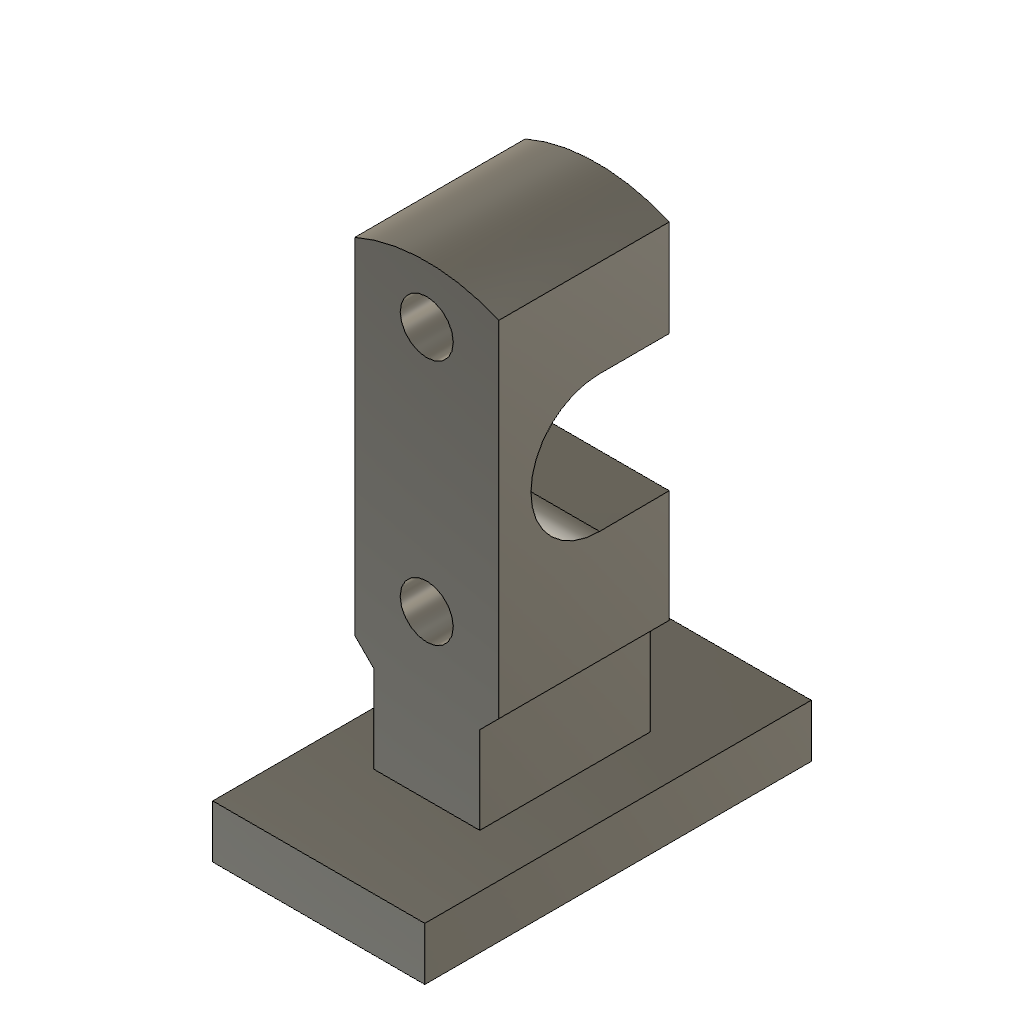
body (Autodesk Fusion 360 design; units mm, degrees)
part number: 2026-10-08-13-23-09-316
Autodesk Fusion 360 part; units mm, degrees
sketch "Sketch1" plane through (0, 0, 0) normal (1, 0, 0) x (0, 1, 0)
  line L0 (0, 0) -> (90, 0)
  line L1 (90, 190) -> (0, 190)
  line L2 (0, 190) -> (0, 0)
  line L3 (90, 0) -> (90, 59.2435)
  line L4 (90, 95) -> (89, 95)
  line L5 (53, 131) -> (90, 131)
  line L6 (53.2376, 59.0008) -> (90, 59.2435)
  arc A0 (53, 131) -> (53.2376, 59.0008) centre (53, 95) ccw
  line L7 (90, 0) -> (90, 59.2435)
  line L8 (90, 131) -> (90, 190)
  line L9 (0, 0) -> (90, 0)
  line L10 (90, 0) -> (90, -56)
  line L11 (90, -56) -> (0, -56)
  line L12 (0, -56) -> (0, 0)
  line L13 (90, -56) -> (147, -56)
  line L14 (147, -56) -> (147, -84)
  line L15 (147, -84) -> (90, -84)
  line L16 (0, -56) -> (-57, -56)
  line L17 (-57, -56) -> (-57, -84)
  line L18 (-57, -84) -> (0, -84)
  line L19 (-57, -56) -> (147, -56)
  line L20 (147, -56) -> (147, -84)
  line L21 (147, -84) -> (-57, -84)
  line L22 (-57, -84) -> (-57, -56)
  dimension "d1" = 90
  dimension "d2" = 190
  dimension "d3" = 95
  dimension "d4" = 37
  dimension "d5" = 72
  dimension "d6" = 90
  dimension "d7" = 56
  dimension "d8" = 57
  dimension "d9" = 28
  dimension "d10" = 57
  dimension "d11" = 28
  constraint horizontal L0
  constraint vertical L7
  constraint horizontal L1
  constraint vertical L2
  constraint coincident L0.start L2.end
  constraint perpendicular L0 L3
  constraint perpendicular L4 L7
  constraint perpendicular L5 L8
  constraint tangent L5 A0
  constraint tangent L6 A0
  constraint collinear L7 L8
  constraint horizontal L9
  constraint vertical L10
  constraint horizontal L11
  constraint vertical L12
  constraint horizontal L13
  constraint vertical L14
  constraint horizontal L15
  constraint horizontal L16
  constraint vertical L17
  constraint horizontal L18
  constraint horizontal L19
  constraint vertical L20
  constraint horizontal L21
  constraint vertical L22
  measures "d1" distance of L0.start L0.end
  measures "d2" distance of L0.start L1.end
  measures "d3" distance of L0.end L4.start
  measures "d4" distance of L4.start A0.centre
  measures "d5" diameter of A0
  measures "d6" distance of L0.start L0.end
  measures "d7" distance of L0.start L11.end
  measures "d8" distance of L10.end L13.end
  measures "d9" distance of L10.end L15.end
  measures "d10" distance of L11.end L16.end
  measures "d11" distance of L11.end L18.end
extrude "Extrude1" add sketch "Sketch1" along normal blind 76 contours L0 L1 L2 L3 L5 L6 A0 L7 L8 L9
sketch "Sketch2" plane through (0, 0, 0) normal (0, -1, 0) x (1, 0, 0)
  line L0 (0, 190) -> (0, 0)
  line L1 (0, 0) -> (76, 0)
  line L2 (76, 0) -> (76, 190)
  line L3 (76, 190) -> (0, 190)
  line L4 (76, 0) -> (66, -10)
  line L5 (76, 0) -> (52.0292, 0) construction
  line L6 (0, 0) -> (10, -10)
  line L7 (0, 0) -> (34.0699, 0) construction
  line L8 (0, 0) -> (10, 0)
  line L9 (10, 0) -> (10, 10)
  line L10 (10, 10) -> (0, 10)
  line L11 (0, 10) -> (0, 0)
  line L12 (10, 0) -> (66, 0)
  line L13 (66, -10) -> (66, -56)
  line L14 (66, -56) -> (10, -56)
  line L15 (10, -56) -> (10, -10)
  dimension "d14" = 45
  dimension "d15" = 45
  dimension "d16" = 10
  dimension "d17" = 10
  dimension "d18" = 56
  dimension "d19" = 56
  constraint horizontal L5
  constraint coincident L1.end L2.start
  constraint horizontal L7
  constraint coincident L0.end L1.start
  constraint horizontal L8
  constraint vertical L9
  constraint horizontal L10
  constraint vertical L11
  constraint horizontal L12
  constraint vertical L13
  constraint horizontal L14
  constraint vertical L15
  measures "d14" angle of L4 L5
  measures "d15" angle of L6 L7
  measures "d16" distance of L0.end L8.end
  measures "d17" distance of L0.end L10.end
  measures "d18" distance of L8.end L12.end
  measures "d19" distance of L8.end L14.end
extrude "Extrude2" add sketch "Sketch2" against normal blind 90 contours L1 L4 L6 L8 L12 L13 L14 L15
sketch "Sketch3" plane through (66, 0, 0) normal (1, 0, 0) x (0, 1, 0)
  line L0 (0, -10) -> (0, -56)
  line L1 (0, -56) -> (90, -56)
  line L2 (90, -56) -> (90, -10)
  line L3 (90, -10) -> (0, -10)
  line L4 (0, -56) -> (-57, -56)
  line L5 (-57, -56) -> (-57, -84)
  line L6 (-57, -84) -> (0, -84)
  line L7 (-57, -56) -> (147, -56)
  line L8 (147, -56) -> (147, -84)
  line L9 (147, -84) -> (-57, -84)
  line L10 (-57, -84) -> (-57, -56)
  dimension "d22" = 57
  dimension "d23" = 28
  dimension "d24" = 204
  dimension "d25" = 28
  constraint horizontal L4
  constraint vertical L5
  constraint horizontal L6
  constraint coincident L0.end L1.start
  constraint horizontal L7
  constraint vertical L8
  constraint horizontal L9
  constraint vertical L10
  measures "d22" distance of L0.end L4.end
  measures "d23" distance of L0.end L6.end
  measures "d24" distance of L4.end L7.end
  measures "d25" distance of L4.end L5.end
extrude "Extrude3" add sketch "Sketch3" along normal blind 28 and the other way blind 84 contours L1 L4 L5 L6 L7 L8 L9 L10
sketch "Sketch4" plane through (0, 0, 0) normal (0, -1, 0) x (1, 0, 0)
  line L0 (0, 190) -> (0, 0)
  line L1 (0, 0) -> (10, -10)
  line L2 (10, -10) -> (10, -56)
  line L3 (10, -56) -> (66, -56)
  line L4 (66, -56) -> (66, -10)
  line L5 (66, -10) -> (76, 0)
  line L6 (76, 0) -> (76, 190)
  line L7 (76, 190) -> (0, 190)
  line L8 (0, 190) -> (38, 190)
  line L9 (38, 190) -> (38, 160)
  line L10 (38, 160) -> (0, 160)
  line L11 (0, 160) -> (0, 190)
  circle A0 centre (38, 160) radius 14
  line L12 (38, 160) -> (38, 30)
  circle A1 centre (38, 30) radius 14
  dimension "d30" = 38
  dimension "d31" = 30
  dimension "d32" = 28
  dimension "d33" = 130
  dimension "d34" = 28
  constraint horizontal L8
  constraint vertical L9
  constraint horizontal L10
  constraint vertical L11
  constraint coincident L0.start L7.end
  constraint coincident L9.end L10.start
  constraint perpendicular L10 L12
  constraint coincident L12.end A1.centre
  measures "d30" distance of L0.start L8.end
  measures "d31" distance of L0.start L10.end
  measures "d32" diameter of A0
  measures "d33" distance of L9.end L12.end
  measures "d34" diameter of A1
extrude "Extrude4" cut sketch "Sketch4" against normal blind 325 contours L9 L10 A0 | L10 A0 L12 | L9 A0 L12 | A1
sketch "Sketch5" plane through (0, 0, 0) normal (0, -1, 0) x (1, 0, 0)
  circle A0 centre (38, 160) radius 14
  circle A1 centre (38, 30) radius 14
  line L0 (0, 190) -> (0, 0)
  line L1 (0, 0) -> (10, -10)
  line L2 (10, -10) -> (10, -56)
  line L3 (10, -56) -> (66, -56)
  line L4 (66, -56) -> (66, -10)
  line L5 (66, -10) -> (76, 0)
  line L6 (76, 0) -> (76, 190)
  line L7 (76, 190) -> (0, 190)
  line L8 (0, 190) -> (0, 95)
  line L9 (0, 95) -> (38, 95)
  circle A2 centre (38, 95) radius 95
  dimension "d37" = 95
  dimension "d38" = 38
  dimension "d39" = 190
  constraint coincident L0.start L7.end
  constraint perpendicular L7 L8
  constraint perpendicular L6 L9
  constraint coincident L9.end A2.centre
  measures "d37" distance of L0.start L8.end
  measures "d38" distance of L8.end L9.end
  measures "d39" diameter of A2
extrude "Extrude5" cut sketch "Sketch5" against normal blind 175 contours L0 L7 L8 A2 | L6 L7 A2
